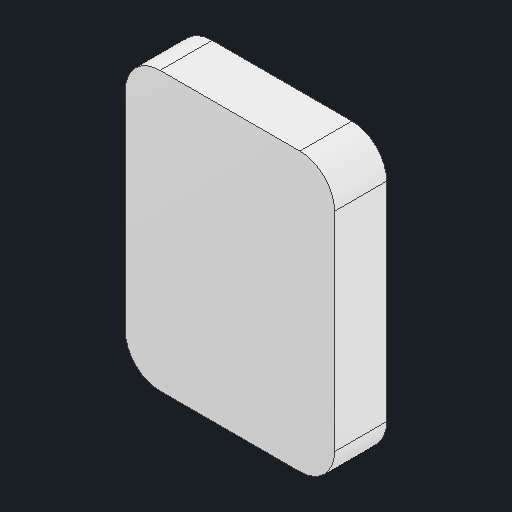
# Autodesk Inventor part: Part4
Saved by Autodesk Inventor 2027.1 (Build 311270010, 270A)
## iProperties
Created: 2024-04-23
Part Number: Part4
Material: ABS Plastic
Document SubType Name: Modeling
Designer: - LENOVO -
Density: 1.06 g/cm^3
Appearance: Smooth - White
Author: - LENOVO -
Autodesk Inventor part; units mm, degrees
ref_plane "YZ Plane" through (0, 0, 0) normal (1, 0, 0) x (0, 1, 0)
ref_plane "XZ Plane" through (0, 0, 0) normal (0, 1, 0) x (-1, 0, 0)
ref_plane "XY Plane" through (0, 0, 0) normal (0, 0, 1) x (1, 0, 0)
sketch "Sketch1" plane through (0, 0, 0) normal (0, 0, 1) x (1, 0, 0)
  line L0 (6.2477, 2.5725) -> (3.837, 2.5725)
  line L1 (3.837, 2.5725) -> (3.837, -0.6269)
  line L2 (3.837, -0.6269) -> (6.2477, -0.6269)
  line L3 (6.2477, -0.6269) -> (6.2477, 2.5725)
  point P0 (0, 0)
  constraints: 8 end point, 2 parallel, 1 horizontal, 1 perpendicular
extrude "Extrusion1" add sketch "Sketch1" along normal blind 0.6
fillet "Fillet1" radius 0.4 4 edges at (3.837, 2.5725, 0.3) (3.837, -0.6269, 0.3) (6.2477, -0.6269, 0.3) (6.2477, 2.5725, 0.3)
body "Solid1"
